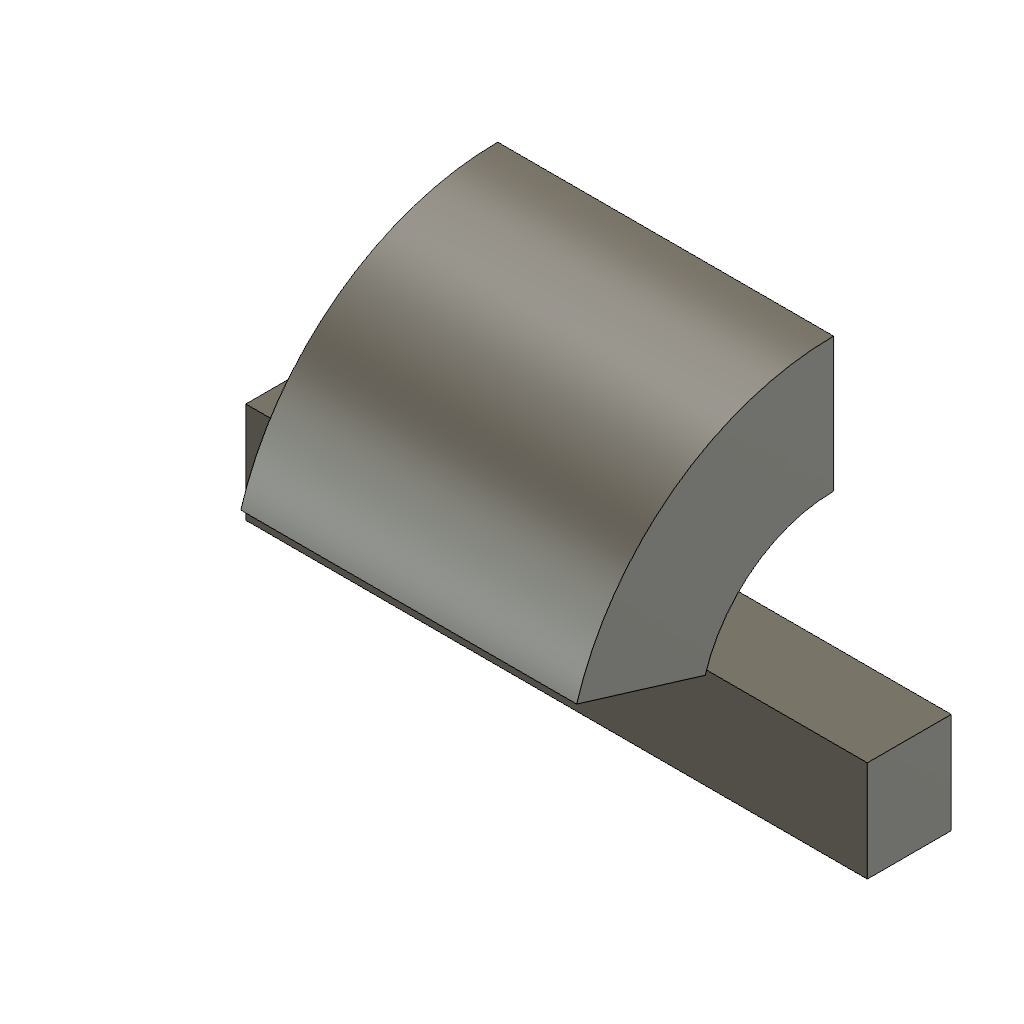
brep_edge_offset_x (Autodesk Fusion 360 design; units mm, degrees)
part number: 2026-10-20-23-14-51-206
Autodesk Fusion 360 part; units mm, degrees
sketch "AxisSupportSketch" plane through (0, 0, 0) normal (0, 0, 1) x (1, 0, 0)
  line L0 (11, -6) -> (48, -6)
  line L1 (48, -6) -> (48, 0)
  line L2 (48, 0) -> (11, 0)
  line L3 (11, 0) -> (11, -6)
extrude "AxisSeedExtrusion" add sketch "AxisSupportSketch" along normal blind 5 makes body 1
sketch "AxisProbeProfile" plane through (0, 0, 0) normal (0, 0, 1) x (1, 0, 0)
  line L0 (21, 8) -> (41, 8)
  line L1 (41, 8) -> (41, 16)
  line L2 (41, 16) -> (21, 16)
  line L3 (21, 16) -> (21, 8)
revolve "ProbeAxisRevolve" add sketch "AxisProbeProfile" angle 73 about axis through (48, 0, 0) along (1, 0, 0) separate body makes body 2
named bodies: "AxisSeedBody"
